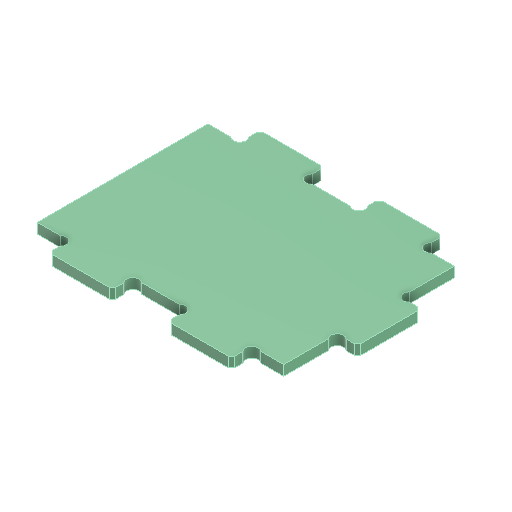
# Autodesk Inventor part: CUT_FR4_Waveguide_Side_Plate
Saved by Autodesk Inventor 2026.1 (Build 301233000, 233)
## iProperties
Created: 2025-11-04
Part Number: CUT_FR4_Waveguide_Side_Plate
Material: Generic
Document SubType Name: Modeling
Designer: User
Density: 1 g/cm^3
Appearance: Smooth - Dark Sea Green
Author: User
Autodesk Inventor part; units mm, degrees
ref_plane "YZ Plane" through (0, 0, 0) normal (1, 0, 0) x (0, 1, 0)
ref_plane "XZ Plane" through (0, 0, 0) normal (0, 1, 0) x (-1, 0, 0)
ref_plane "XY Plane" through (0, 0, 0) normal (0, 0, 1) x (1, 0, 0)
sketch "Sketch1" plane through (0, 0, 0) normal (0, 1, 0) x (-1, 0, 0)
  line L0 (19.35, 13.4) -> (-19.35, 13.4)
  line L1 (-19.35, 13.4) -> (-19.35, -13.4)
  line L2 (-19.35, -13.4) -> (19.35, -13.4)
  line L3 (19.35, -13.4) -> (19.35, 13.4)
  line L4 (-24.35, 18.4) -> (24.35, 18.4)
  line L5 (24.35, 18.4) -> (24.35, -18.4)
  line L6 (24.35, -18.4) -> (-24.35, -18.4)
  line L7 (-24.35, -18.4) -> (-24.35, 18.4)
  line L8 (19.35, 13.4) -> (19.35, 18.4)
  line L9 (19.35, -13.4) -> (19.35, -18.4)
  line L10 (-19.35, 13.4) -> (-19.35, 18.4)
  line L11 (-19.35, -13.4) -> (-19.35, -18.4)
  point P0 (0, 0)
  dimension "d0" = 38.7
  dimension "d1" = 26.8
  dimension "d2" = 19.35
  dimension "d3" = 13.4
  dimension "d4" = 5
  constraints: 24 end point, 6 point on line, 4 parallel, 4 perpendicular, 1 horizontal, 3 other
  measures "d0" distance of L1.end L2.end
  measures "d1" distance of L0.end L1.end
  measures "d2" distance from line of L1 point (0, 0)
  measures "d3" distance from line of L0 point (0, 0)
  measures "d4" distance between parallel lines of L0 L4
extrude "Extrusion1" add sketch "Sketch1" along normal blind 1.6 contours L3 L2 L1 L0
sketch "Sketch2" plane through (-19.35, 0, 13.4) normal (0, 0, 1) x (1, 0, 0)
  line L0 (0, 1.6) -> (38.7, 1.6) construction
  line L1 (0, 0) -> (38.7, 0) construction
  line L2 (5, 1.6) -> (15, 1.6)
  line L3 (15, 1.6) -> (15, 0)
  line L4 (15, 0) -> (5, 0)
  line L5 (5, 0) -> (5, 1.6)
  dimension "d7" = 5
  dimension "d8" = 10
  constraints: 8 end point, 2 collinear, 2 parallel, 1 perpendicular
  measures "d7" distance from line of L5 L0.start
  measures "d8" distance between parallel lines of L3 L5
sketch "Sketch3" plane through (-19.35, 0, 13.4) normal (0, 0, 1) x (1, 0, 0)
  line L0 (0, 1.6) -> (38.7, 1.6) projected
extrude "Extrusion2" add sketch "Sketch2" along normal blind 3.2
pattern_linear "Rectangular Pattern1" count 2 spacing 18.7 along (1, 0, 0) of "Extrusion2"
sketch "Sketch4" plane through (0, 1.6, 0) normal (0, 1, 0) x (1, 0, 0)
  line L0 (-4.35, -13.4) -> (4.35, -13.4) construction
  line L1 (-4.35, -13.4) -> (-4.35, -16.6) construction
  circle A0 centre (-3.6429, -14.1071) radius 1
  line L2 (-19.35, -13.4) -> (-14.35, -13.4) construction
  line L3 (-14.35, -13.4) -> (-14.35, -16.6) construction
  circle A1 centre (-15.0571, -14.1071) radius 1
  line L4 (14.35, -13.4) -> (19.35, -13.4) construction
  line L5 (14.35, -13.4) -> (14.35, -16.6) construction
  circle A2 centre (15.0571, -14.1071) radius 1
  line L6 (4.35, -13.4) -> (4.35, -16.6) construction
  circle A3 centre (3.6429, -14.1071) radius 1
  dimension "d15" = 2
  dimension "d17" = 2
  dimension "d19" = 2
  dimension "d21" = 2
  dimension "d14" = 45
  dimension "d16" = 45
  dimension "d18" = 45
  dimension "d20" = 45
  constraints: 4 coincident, 12 other
extrude "Extrusion3" cut sketch "Sketch4" against normal up to surface (1.6 mm away)
chamfer "Chamfer1" distance 0.5 angle 45 4 edges at (-14.35, 0.8, 16.6) (-4.35, 0.8, 16.6) (4.35, 0.8, 16.6) (14.35, 0.8, 16.6)
sketch "Sketch5" plane through (19.35, 0, -13.4) normal (0, 0, -1) x (-1, 0, 0)
  line L0 (0, 0) -> (38.7, 0) construction
  line L1 (0, 1.6) -> (38.7, 1.6) construction
  line L2 (5, 0) -> (15, 0)
  line L3 (15, 0) -> (15, 1.6)
  line L4 (15, 1.6) -> (5, 1.6)
  line L5 (5, 1.6) -> (5, 0)
  dimension "d27" = 5
  dimension "d28" = 10
  constraints: 8 end point, 2 collinear, 2 parallel, 1 perpendicular
  measures "d27" distance from line of L5 L0.start
  measures "d28" distance between parallel lines of L3 L5
sketch "Sketch6" plane through (19.35, 0, -13.4) normal (0, 0, -1) x (-1, 0, 0)
  line L0 (0, 0) -> (38.7, 0) projected
extrude "Extrusion4" add sketch "Sketch5" along normal blind 3.2
pattern_linear "Rectangular Pattern2" count 2 spacing 18.7 along (-1, 0, 0) of "Extrusion4"
sketch "Sketch7" plane through (0, 0, 0) normal (0, -1, 0) x (1, 0, 0)
  line L0 (19.35, -13.4) -> (14.35, -13.4) construction
  line L1 (14.35, -13.4) -> (14.35, -16.6) construction
  circle A0 centre (15.0571, -14.1071) radius 1
  line L2 (4.35, -13.4) -> (-4.35, -13.4) construction
  line L3 (4.35, -13.4) -> (4.35, -16.6) construction
  circle A1 centre (3.6429, -14.1071) radius 1
  line L4 (-4.35, -13.4) -> (-4.35, -16.6) construction
  circle A2 centre (-3.6429, -14.1071) radius 1
  line L5 (-14.35, -13.4) -> (-19.35, -13.4) construction
  line L6 (-14.35, -13.4) -> (-14.35, -16.6) construction
  circle A3 centre (-15.0571, -14.1071) radius 1
  dimension "d35" = 2
  dimension "d37" = 2
  dimension "d39" = 2
  dimension "d41" = 2
  dimension "d34" = 45
  dimension "d36" = 45
  dimension "d38" = 45
  dimension "d40" = 45
  constraints: 4 coincident, 12 other
extrude "Extrusion5" cut sketch "Sketch7" against normal up to surface (1.6 mm away)
chamfer "Chamfer2" distance 0.5 angle 45 4 edges at (4.35, 0.8, -16.6) (14.35, 0.8, -16.6) (-14.35, 0.8, -16.6) (-4.35, 0.8, -16.6)
sketch "Sketch8" plane through (19.35, 0, 13.4) normal (1, 0, 0) x (0, 0, -1)
  line L0 (0, 0) -> (26.8, 0) construction
  line L1 (0, 1.6) -> (26.8, 1.6) construction
  line L2 (8.4, 0) -> (18.4, 0)
  line L3 (18.4, 0) -> (18.4, 1.6)
  line L4 (18.4, 1.6) -> (8.4, 1.6)
  line L5 (8.4, 1.6) -> (8.4, 0)
  dimension "d47" = 8.4
  dimension "d48" = 10
  constraints: 8 end point, 2 collinear, 2 parallel, 1 perpendicular
  measures "d47" distance from line of L5 L0.start
  measures "d48" distance between parallel lines of L3 L5
extrude "Extrusion6" add sketch "Sketch8" along normal blind 3.2
sketch "Sketch10" plane through (0, 0, 0) normal (0, -1, 0) x (1, 0, 0)
  line L0 (19.35, 13.4) -> (19.35, 5) construction
  line L1 (19.35, 5) -> (22.55, 5) construction
  circle A0 centre (20.0571, 5.7071) radius 1
  line L2 (19.35, -5) -> (19.35, -13.4) construction
  line L3 (19.35, -5) -> (22.55, -5) construction
  circle A1 centre (20.0571, -5.7071) radius 1
  dimension "d52" = 2
  dimension "d54" = 2
  dimension "d51" = 45
  dimension "d53" = 45
  constraints: 2 coincident, 6 other
extrude "Extrusion7" cut sketch "Sketch10" against normal up to surface (1.6 mm away)
chamfer "Chamfer3" distance 0.5 angle 45 2 edges at (22.55, 0.8, -5) (22.55, 0.8, 5)
equation "\"d2\" = 0.5 * d0"
equation "\"d3\" = 0.5 * d1"
body "Solid1"
